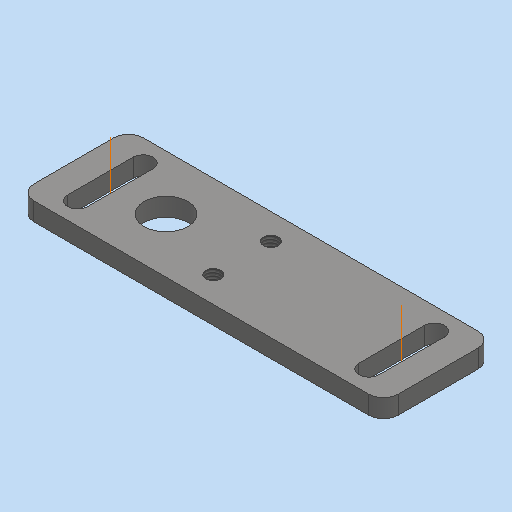
# Autodesk Inventor part: MM0937AN200_G27_116
Saved by Autodesk Inventor 2023.3 (Build 273359000, 359)
## iProperties
RuleStatus: InUse
Created: 2021-07-22
Part Number: MM0937AN200_G27_116
Material: 1.4301 X5CrNi18-10
Description: =<RBPARTNOTITLE2>
Document SubType Name: Blech
Designer: frt9bw
Mass: 102.082 g
Surface Area: 73.1843 cm^2
Volume: 13.004 cm^3
Density: 7.85 g/cm^3
Sheet Metal Rule: Standard_mm
Appearance: Stahl - rostfrei AnP
AnP_Kategorie: 1
AnP_Material: =<Material>
MaxAbmaße: 5 x 30 x 100 (FM)
AnP_TemplVers: 20200821
RBDOCUMENTTYPE: DRF
RBDOCUMENTVERSION: 00
RBDRAWINGMAINSCALE: 1:1
RBDRAWINGMISSINGSPEC: --
RBDRAWINGVOLUME: --
RBDSV1: 0850
RBGBEDGESIN1: +0,5
RBGBEDGESIN2: +0,2
RBGBEDGESOUT1: -0,3
RBGBEDGESOUT2: -0,1
RBMATERIAL: =<Material>
RBMATMEETS: --
RBMATNO: =<Part Number>
RBPARTMADEOF: 5 x 30 x 100 (FM)
RBPARTNO: SIEHE MNR
RBPARTNOTITLE1: manufactured part
RBPARTNOTITLE2: Anfertigungsteil
RBPARTSAFETYINDICATOR: --
RBSURFACE: --
RBSURFACE2: --
RBZEDGESNORM: ISO13715:2002-06
RBZGENDIMCLASS: m
RBZGENDIMNORM: ISO 2768-1:1989-11
RBZGENGEOCLASS: H
RBZGENGEONORM: ISO 2768-2:1989-11
RBZSURFACENORM: ISO13D2:2002-02
RBZTOLERANCENORM: ISO 14405-1:2010-12
Author: frt9bw
Keywords: =<RBPARTMADEOF>
Comments: =<RBSURFACE2>
Revision Number: 01
Autodesk Inventor part; units mm, degrees
ref_plane "YZ Plane" through (0, 0, 0) normal (1, 0, 0) x (0, 1, 0)
ref_plane "XZ Plane" through (0, 0, 0) normal (0, 1, 0) x (-1, 0, 0)
ref_plane "XY Plane" through (0, 0, 0) normal (0, 0, 1) x (1, 0, 0)
sketch "Skizze1" plane through (0, 0, 0) normal (0, 0, 1) x (1, 0, 0)
  line L0 (0, 0) -> (100, 0)
  line L1 (100, 0) -> (100, 30)
  line L2 (100, 30) -> (0, 30)
  line L3 (0, 30) -> (0, 0)
  dimension "d0" = 100
  dimension "d1" = 30
  measures "d0" distance of L2.end L1.end
  measures "d1" distance of L1.end L0.end
extrude "Grobblech1" add sketch "Skizze1" along normal blind 5
sketch "Skizze3" plane through (0, 0, 5) normal (0, 0, 1) x (1, 0, 0)
  line L0 (0, 0) -> (0, 30) projected
  line L1 (0, 30) -> (100, 30) projected
  line L2 (100, 0) -> (0, 0) projected
  point P0 (46.2, 7.1)
  point P1 (46.2, 22.9)
  dimension "d38" = 15.8
  dimension "d39" = 7.1
  dimension "d40" = 46.2
  constraints: 1 vertical alignment
  measures "d38" distance of point (46.2, 7.1) point (46.2, 22.9)
  measures "d39" distance from line of point (46.2, 7.1) L2
  measures "d40" distance from line of L0 point (46.2, 7.1)
hole "Bohrung2" at (46.2, 7.1, 5) at (46.2, 22.9, 5) direction (0, 0, -1) diameter 4.134 end through all thread size "M5x0.8" designation "M5" class "6H" standard "ISO Metric profile"
sketch "Skizze4" plane through (0, 0, 5) normal (0, 0, 1) x (1, 0, 0)
  line L0 (10, 24) -> (10, 6) construction
  line L1 (7.25, 24) -> (7.25, 6)
  line L2 (12.75, 6) -> (12.75, 24)
  arc A0 (12.75, 24) -> (7.25, 24) centre (10, 24) ccw
  arc A1 (7.25, 6) -> (12.75, 6) centre (10, 6) ccw
  line L3 (90, 24) -> (90, 6) construction
  line L4 (87.25, 24) -> (87.25, 6)
  line L5 (92.75, 6) -> (92.75, 24)
  arc A2 (92.75, 24) -> (87.25, 24) centre (90, 24) ccw
  arc A3 (87.25, 6) -> (92.75, 6) centre (90, 6) ccw
  line L6 (0, 30) -> (100, 30) projected
  line L7 (0, 0) -> (0, 30) projected
  line L8 (100, 30) -> (100, 0) projected
  point P0 (10, 15)
  point P1 (90, 15)
  dimension "d29" = 5.5
  dimension "d30" = 5.5
  dimension "d31" = 15
  dimension "d32" = 10
  dimension "d33" = 10
  dimension "d34" = 18
  constraints: 16 end point, 8 point on circle, 8 tangent, 4 centre point, 3 horizontal alignment, 3 parallel, 2 midpoint, 1 vertical
  measures "d29" diameter of A1
  measures "d30" diameter of A3
  measures "d31" distance from line of point (10, 15) L6
  measures "d32" distance from line of point (10, 15) L7
  measures "d33" distance from line of L8 point (90, 15)
  measures "d34" distance of L0.end L0.start
extrude "Extrusion1" cut sketch "Skizze4" against normal through all
fillet "Rundung1" radius 4 4 edges at (0, 30, 2.5) (0, 0, 2.5) (100, 0, 2.5) (100, 30, 2.5)
sketch "Skizze5" plane through (0, 0, 5) normal (0, 0, 1) x (1, 0, 0)
  line L0 (0, 4) -> (0, 26) projected
  line L1 (96, 0) -> (4, 0) projected
  point P0 (0, 0)
  point P1 (25.3, 15)
  dimension "d41" = 25.3
  dimension "d42" = 15
  measures "d41" distance from line of point (25.3, 15) L0
  measures "d42" distance from line of point (25.3, 15) L1
hole "Bohrung3" at (25.3, 15, 5) direction (0, 0, -1) diameter 12 end through all
equation "\"d48\" = Stärke"
equation "\"d2\" = Stärke"
equation "\"Biegeradius\" = Stärke"
equation "\"BreiteBiegungsfreistellung\" = Stärke"
equation "\"TiefeBiegungsfreistellung\" = 0.5 * Stärke"
equation "\"Übergangsradius\" = Biegeradius"
equation "\"JacobiRadiusGröße\" = Biegeradius"
equation "\"Abstandsgröße\" = Stärke"
equation "\"Stärke\" = 5"
